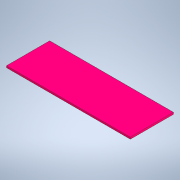
# Autodesk Inventor part: stg_dr_cutie_superioara
Saved by Autodesk Inventor 2022.6 (Build 266554000, 554)
## iProperties
Created: 2025-06-18
Part Number: stg_dr_cutie_superioara
Material: Generic
Document SubType Name: Modeling
Designer: Dragos Macovei
Density: 1 g/cm^3
Appearance: Default
Author: Dragos Macovei
Autodesk Inventor part; units mm, degrees
ref_plane "YZ Plane" through (0, 0, 0) normal (1, 0, 0) x (0, 1, 0)
ref_plane "XZ Plane" through (0, 0, 0) normal (0, 1, 0) x (-1, 0, 0)
ref_plane "XY Plane" through (0, 0, 0) normal (0, 0, 1) x (1, 0, 0)
sketch "Sketch1" plane through (0, 0, 0) normal (0, 1, 0) x (-1, 0, 0)
  line L0 (0, 0) -> (1212, 0)
  line L1 (1212, 0) -> (1212, 422)
  line L2 (1212, 422) -> (0, 422)
  line L3 (0, 422) -> (0, 0)
  dimension "d0" = 1212
  dimension "d1" = 422
  constraints: 8 end point, 2 parallel, 1 horizontal, 1 perpendicular
  measures "d0" distance of L2.end L1.end
  measures "d1" distance between parallel lines of L0 L2
extrude "Extrusion1" add sketch "Sketch1" along normal blind 18
body "Solid1"
